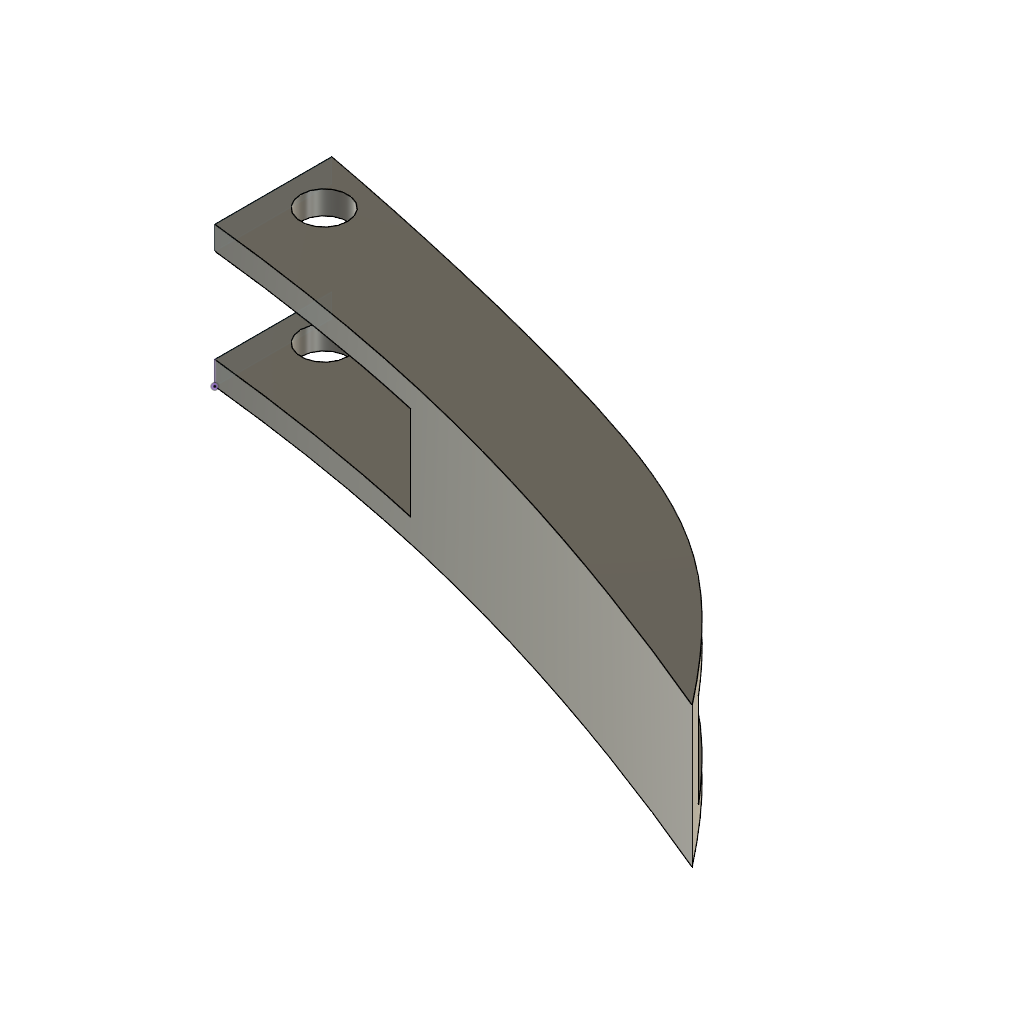
bottom trigger (Autodesk Fusion 360 design; units mm, degrees)
Autodesk Fusion 360 part; units mm, degrees
derive "DerivedContext1" from "assembly trigger v6"
sketch "Sketch1" plane through (0, 0, 0) normal (0, 0, 1) x (1, 0, 0)
  line L0 (70, 0) -> (0, 0) construction
  line L1 (0, 0) -> (0, 19) construction
  line L2 (0, 19) -> (0, 31.5)
  spline S0 degree 5 poles (0, 19) (3.7774, 18.5857) (11.047, 17.6563) (21.0963, 15.9597) (33.0212, 13.1761) (46.292, 9.1181) (56.1059, 5.5879) (63.1632, 2.8329) (67.7421, 0.9517) (70, 0) knots 0 0 0 0 0 0 0.2 0.4 0.6 0.8 1 1 1 1 1 1
  line L3 (-9.5744, 20.05) -> (9.5744, 17.95)
  spline S1 degree 5 poles (0, 31.5) (1.2479, 31.2649) (3.7995, 30.7712) (7.7943, 29.9605) (13.4574, 28.7383) (21.0918, 26.9563) (29.128, 24.9178) (37.3244, 22.5914) (44.9227, 20.0618) (51.5658, 17.1401) (57.585, 13.3042) (62.3122, 9.0275) (66.0506, 4.9007) (68.6634, 1.7073) (70, 0) knots 0 0 0 0 0 0 0.1 0.2 0.3 0.4 0.5 0.6 0.7 0.8 0.9 1 1 1 1 1 1
  line L4 (62.9488, 9.0069) -> (77.0512, -9.0069)
  line L5 (27.798, 25.3994) -> (45.0092, 20.1534)
  line L6 (0, 19) -> (0, 22)
  spline S2 degree 5 poles (-0.0005, 21.9997) (3.6175, 21.6029) (10.5796, 20.7113) (20.2024, 19.0799) (31.6183, 16.3979) (44.3187, 12.4831) (53.7089, 9.0754) (60.4606, 6.4154) (64.8409, 4.5988) (67.0008, 3.6796) knots 0 0 0 0 0 0 0.2 0.4 0.6 0.8 1 1 1 1 1 1
  line L7 (-9.5749, 23.0497) -> (9.5739, 20.9497)
  line L8 (25, 17.8107) -> (25, 14.896)
  point P0 (36.4036, 22.7764)
  dimension "d1" = 70
  dimension "d3" = 19
  dimension "d4" = 12.5
  dimension "d16" = 3
  dimension "d19" = 25
  constraint horizontal L0
  constraint coincident L0.end L1.start
  constraint perpendicular L0 L1
  constraint midpoint L1.end L3
  constraint midpoint L0.start L4
  constraint midpoint P0 L5
  constraint parallel L2 L6
  constraint midpoint S2.start L7
  constraint coincident S1 S2.end
  constraint coincident S2 L8.start
  constraint coincident S0 L8.end
  constraint parallel L2 L8
  measures "d1" distance of L0.start L0.end
  measures "d3" distance of L0.end L1.end
  measures "d4" distance of L1.end L2.end
  measures "d16" distance of L1.end L6.end
  measures "d19" distance of L6 L8
extrude "Extrude1" add sketch "Sketch1" along normal mid plane 15
extrude "Extrude3" cut sketch "Sketch1" along normal mid plane 10 contours L2 S0 L6 S2 L8 | L2 S1 S2
sketch "Sketch8" plane through (0, 0, 0) normal (-1, 0, 0) x (0, -1, 0)
  line L0 (-31.5, 5) -> (-19, 5)
  line L1 (-19, -5) -> (-31.5, -5)
  line L2 (-31.5, -5) -> (-31.5, -7.5)
  line L3 (-31.5, -7.5) -> (-19, -7.5)
  line L4 (-19, 5) -> (-19, 7.5)
  line L5 (-19, 7.5) -> (-31.5, 7.5)
  line L6 (-31.5, 7.5) -> (-31.5, 5)
  line L7 (-19, -7.5) -> (-19, -5)
sketch "Sketch10" plane through (0, 0, 7.5) normal (0, 0, 1) x (-1, 0, 0)
  spline S0 degree 5 poles (0, -19) (-3.7774, -18.5857) (-11.047, -17.6563) (-21.0963, -15.9597) (-33.0212, -13.1761) (-46.292, -9.1181) (-56.1059, -5.5879) (-63.1632, -2.8329) (-67.7421, -0.9517) (-70, 0) knots 0 0 0 0 0 0 0.2 0.4 0.6 0.8 1 1 1 1 1 1
  spline S1 degree 5 poles (-70, 0) (-68.6634, -1.7073) (-66.0506, -4.9007) (-62.3122, -9.0275) (-57.585, -13.3042) (-51.5658, -17.1401) (-44.9227, -20.0618) (-37.3244, -22.5914) (-29.128, -24.9178) (-21.0918, -26.9563) (-13.4574, -28.7383) (-7.7943, -29.9605) (-3.7995, -30.7712) (-1.2479, -31.2649) (0, -31.5) knots -1 -1 -1 -1 -1 -1 -0.9 -0.8 -0.7 -0.6 -0.5 -0.4 -0.3 -0.2 -0.1 0 0 0 0 0 0
  line L0 (0, -31.5) -> (0, -19)
  circle A0 centre (-4.3353, -26.3526) radius 2.5
  dimension "d23" = 5
  measures "d23" diameter of A0
extrude "Extrude5" cut sketch "Sketch10" against normal blind 16 contours A0
